Autodesk Fusion 360 part; units mm, degrees
(part 2 of 2)
sketch "草图1 (19)" plane through (0, 50, 0) normal (0, 1, 0) x (1, 0, 0) in component "REF_CASE_FAN_CPU_140x140x25"
  line L0 (156.4, -210, -100) -> (296.4, -210, -100)
  line L1 (296.4, -210, -100) -> (296.4, -350, -100)
  line L2 (296.4, -350, -100) -> (156.4, -350, -100)
  line L3 (156.4, -350, -100) -> (156.4, -210, -100)
extrude "140x140x25 fan envelope'" add sketch "草图1 (19)" along normal blind 25 separate body contours L0 L1 L2 L3 in plane through (0, -50, 0) normal (0, 1, 0) makes body 19 in component "REF_CASE_FAN_CPU_140x140x25"
ref_plane "工作平面2" through (0, 50, 0) normal (0, 1, 0) x (0, 0, 1) in component "REF_CASE_FAN_CPU_140x140x25"
sketch "草图2 (18)" plane through (0, 50, 0) normal (0, 1, 0) x (1, 0, 0) in component "REF_CASE_FAN_CPU_140x140x25"
  circle A0 through (291.4, -280, -100) (193.9, -223.7083, -100) (193.9, -336.2917, -100)
extrude "Rotor opening reference'" cut sketch "草图2 (18)" along normal blind 25 contours A0 in plane through (0, -50, 0) normal (0, 1, 0) bodies 19 in component "REF_CASE_FAN_CPU_140x140x25"
ref_plane "工作平面3" through (0, 0, 278) normal (0, 0, 1) x (1, 0, 0) in component "REF_CASE_FAN_CPU_140x140x25"
sketch "草图3 (14)" plane through (0, 0, 278) normal (0, 0, 1) x (1, 0, 0) in component "REF_CASE_FAN_CPU_140x140x25"
  line L0 (159.4, -38) -> (293.4, -38)
  line L1 (293.4, -38) -> (293.4, -36)
  line L2 (293.4, -36) -> (159.4, -36)
  line L3 (159.4, -36) -> (159.4, -38)
extrude "Rotor reference spoke horizontal'" add sketch "草图3 (14)" along normal blind 4 bodies 19 in component "REF_CASE_FAN_CPU_140x140x25"
ref_plane "工作平面4" through (0, 0, 213) normal (0, 0, 1) x (1, 0, 0) in component "REF_CASE_FAN_CPU_140x140x25"
sketch "草图4 (14)" plane through (0, 0, 213) normal (0, 0, 1) x (1, 0, 0) in component "REF_CASE_FAN_CPU_140x140x25"
  line L0 (224.4, -38) -> (228.4, -38)
  line L1 (228.4, -38) -> (228.4, -36)
  line L2 (228.4, -36) -> (224.4, -36)
  line L3 (224.4, -36) -> (224.4, -38)
extrude "Rotor reference spoke vertical'" add sketch "草图4 (14)" along normal blind 134 bodies 19 in component "REF_CASE_FAN_CPU_140x140x25"
ref_plane "工作平面5" through (0, 38, 0) normal (0, 1, 0) x (0, 0, 1) in component "REF_CASE_FAN_CPU_140x140x25"
sketch "草图5 (14)" plane through (0, 38, 0) normal (0, 1, 0) x (1, 0, 0) in component "REF_CASE_FAN_CPU_140x140x25"
  circle A0 through (242.4, -280, -76) (218.4, -266.1436, -76) (218.4, -293.8564, -76)
extrude "Fan hub reference'" add sketch "草图5 (14)" along normal blind 2 contours A0 in plane through (0, -38, 0) normal (0, 1, 0) bodies 19 in component "REF_CASE_FAN_CPU_140x140x25"
ref_plane "工作平面6" through (0, 50, 0) normal (0, 1, 0) x (0, 0, 1) in component "REF_CASE_FAN_CPU_140x140x25"
sketch "草图6 (10)" plane through (0, 50, 0) normal (0, 1, 0) x (1, 0, 0) in component "REF_CASE_FAN_CPU_140x140x25"
  circle A0 through (166.4, -217.75, -100) (163.025, -215.8014, -100) (163.025, -219.6986, -100)
extrude "Reference fan mounting bore'" cut sketch "草图6 (10)" along normal blind 25 contours A0 in plane through (0, -50, 0) normal (0, 1, 0) bodies 19 in component "REF_CASE_FAN_CPU_140x140x25"
ref_plane "工作平面7" through (0, 50, 0) normal (0, 1, 0) x (0, 0, 1) in component "REF_CASE_FAN_CPU_140x140x25"
sketch "草图7 (7)" plane through (0, 50, 0) normal (0, 1, 0) x (1, 0, 0) in component "REF_CASE_FAN_CPU_140x140x25"
  circle A0 through (166.4, -342.25, -100) (163.025, -340.3014, -100) (163.025, -344.1986, -100)
extrude "Reference fan mounting bore (1)'" cut sketch "草图7 (7)" along normal blind 25 contours A0 in plane through (0, -50, 0) normal (0, 1, 0) bodies 19 in component "REF_CASE_FAN_CPU_140x140x25"
ref_plane "工作平面8" through (0, 50, 0) normal (0, 1, 0) x (0, 0, 1) in component "REF_CASE_FAN_CPU_140x140x25"
sketch "草图8 (6)" plane through (0, 50, 0) normal (0, 1, 0) x (1, 0, 0) in component "REF_CASE_FAN_CPU_140x140x25"
  circle A0 through (290.9, -217.75, -100) (287.525, -215.8014, -100) (287.525, -219.6986, -100)
extrude "Reference fan mounting bore (2)'" cut sketch "草图8 (6)" along normal blind 25 contours A0 in plane through (0, -50, 0) normal (0, 1, 0) bodies 19 in component "REF_CASE_FAN_CPU_140x140x25"
ref_plane "工作平面9" through (0, 50, 0) normal (0, 1, 0) x (0, 0, 1) in component "REF_CASE_FAN_CPU_140x140x25"
sketch "草图9 (6)" plane through (0, 50, 0) normal (0, 1, 0) x (1, 0, 0) in component "REF_CASE_FAN_CPU_140x140x25"
  circle A0 through (290.9, -342.25, -100) (287.525, -340.3014, -100) (287.525, -344.1986, -100)
extrude "Reference fan mounting bore (3)'" cut sketch "草图9 (6)" along normal blind 25 contours A0 in plane through (0, -50, 0) normal (0, 1, 0) bodies 19 in component "REF_CASE_FAN_CPU_140x140x25"
ref_plane "工作平面1" through (0, 0, 279) normal (0, 0, 1) x (1, 0, 0) in component "REF_AIRFLOW_CPU_FRONT_TO_REAR"
sketch "草图1 (20)" plane through (0, 0, 279) normal (0, 0, 1) x (1, 0, 0) in component "REF_AIRFLOW_CPU_FRONT_TO_REAR"
  line L0 (221.4, -75) -> (231.4, -75)
  line L1 (231.4, -75) -> (231.4, -64)
  line L2 (231.4, -64) -> (238.4, -64)
  line L3 (238.4, -64) -> (226.4, -53)
  line L4 (226.4, -53) -> (214.4, -64)
  line L5 (214.4, -64) -> (221.4, -64)
  line L6 (221.4, -64) -> (221.4, -75)
extrude "Front intake direction +Y'" add sketch "草图1 (20)" along normal blind 2 separate body makes body 20 in component "REF_AIRFLOW_CPU_FRONT_TO_REAR"
ref_plane "工作平面1" through (0, 0, 208) normal (0, 0, 1) x (1, 0, 0) in component "REF_BOARD_304.8x243.84_NUMBERED_HOLES"
sketch "草图1 (21)" plane through (0, 0, 208) normal (0, 0, 1) x (1, 0, 0) in component "REF_BOARD_304.8x243.84_NUMBERED_HOLES"
  line L0 (0, 0) -> (304.8, 0)
  line L1 (304.8, 0) -> (304.8, 243.84)
  line L2 (304.8, 243.84) -> (0, 243.84)
  line L3 (0, 243.84) -> (0, 0)
extrude "Motherboard component-side reference" add sketch "草图1 (21)" along normal blind 1.6 separate body makes body 21 in component "REF_BOARD_304.8x243.84_NUMBERED_HOLES"
ref_plane "工作平面2" through (0, 0, 208) normal (0, 0, 1) x (1, 0, 0) in component "REF_BOARD_304.8x243.84_NUMBERED_HOLES"
sketch "草图2 (19)" plane through (0, 0, 208) normal (0, 0, 1) x (1, 0, 0) in component "REF_BOARD_304.8x243.84_NUMBERED_HOLES"
  circle A0 centre (16.51, 233.68) radius 1.98
extrude "Board hole 1" cut sketch "草图2 (19)" along normal blind 1.6 bodies 21 in component "REF_BOARD_304.8x243.84_NUMBERED_HOLES"
ref_plane "工作平面3" through (0, 0, 208) normal (0, 0, 1) x (1, 0, 0) in component "REF_BOARD_304.8x243.84_NUMBERED_HOLES"
sketch "草图3 (15)" plane through (0, 0, 208) normal (0, 0, 1) x (1, 0, 0) in component "REF_BOARD_304.8x243.84_NUMBERED_HOLES"
  circle A0 centre (140.97, 233.68) radius 1.98
extrude "Board hole 2" cut sketch "草图3 (15)" along normal blind 1.6 bodies 21 in component "REF_BOARD_304.8x243.84_NUMBERED_HOLES"
ref_plane "工作平面4" through (0, 0, 208) normal (0, 0, 1) x (1, 0, 0) in component "REF_BOARD_304.8x243.84_NUMBERED_HOLES"
sketch "草图4 (15)" plane through (0, 0, 208) normal (0, 0, 1) x (1, 0, 0) in component "REF_BOARD_304.8x243.84_NUMBERED_HOLES"
  circle A0 centre (298.45, 210.82) radius 1.98
extrude "Board hole 3" cut sketch "草图4 (15)" along normal blind 1.6 bodies 21 in component "REF_BOARD_304.8x243.84_NUMBERED_HOLES"
ref_plane "工作平面5" through (0, 0, 208) normal (0, 0, 1) x (1, 0, 0) in component "REF_BOARD_304.8x243.84_NUMBERED_HOLES"
sketch "草图5 (15)" plane through (0, 0, 208) normal (0, 0, 1) x (1, 0, 0) in component "REF_BOARD_304.8x243.84_NUMBERED_HOLES"
  circle A0 centre (16.51, 78.74) radius 1.98
extrude "Board hole 4" cut sketch "草图5 (15)" along normal blind 1.6 bodies 21 in component "REF_BOARD_304.8x243.84_NUMBERED_HOLES"
ref_plane "工作平面6" through (0, 0, 208) normal (0, 0, 1) x (1, 0, 0) in component "REF_BOARD_304.8x243.84_NUMBERED_HOLES"
sketch "草图6 (11)" plane through (0, 0, 208) normal (0, 0, 1) x (1, 0, 0) in component "REF_BOARD_304.8x243.84_NUMBERED_HOLES"
  circle A0 centre (140.97, 78.74) radius 1.98
extrude "Board hole 5" cut sketch "草图6 (11)" along normal blind 1.6 bodies 21 in component "REF_BOARD_304.8x243.84_NUMBERED_HOLES"
ref_plane "工作平面7" through (0, 0, 208) normal (0, 0, 1) x (1, 0, 0) in component "REF_BOARD_304.8x243.84_NUMBERED_HOLES"
sketch "草图7 (8)" plane through (0, 0, 208) normal (0, 0, 1) x (1, 0, 0) in component "REF_BOARD_304.8x243.84_NUMBERED_HOLES"
  circle A0 centre (298.45, 78.74) radius 1.98
extrude "Board hole 6" cut sketch "草图7 (8)" along normal blind 1.6 bodies 21 in component "REF_BOARD_304.8x243.84_NUMBERED_HOLES"
ref_plane "工作平面8" through (0, 0, 208) normal (0, 0, 1) x (1, 0, 0) in component "REF_BOARD_304.8x243.84_NUMBERED_HOLES"
sketch "草图8 (7)" plane through (0, 0, 208) normal (0, 0, 1) x (1, 0, 0) in component "REF_BOARD_304.8x243.84_NUMBERED_HOLES"
  circle A0 centre (16.51, 6.35) radius 1.98
extrude "Board hole 7" cut sketch "草图8 (7)" along normal blind 1.6 bodies 21 in component "REF_BOARD_304.8x243.84_NUMBERED_HOLES"
ref_plane "工作平面9" through (0, 0, 208) normal (0, 0, 1) x (1, 0, 0) in component "REF_BOARD_304.8x243.84_NUMBERED_HOLES"
sketch "草图9 (7)" plane through (0, 0, 208) normal (0, 0, 1) x (1, 0, 0) in component "REF_BOARD_304.8x243.84_NUMBERED_HOLES"
  circle A0 centre (140.97, 6.35) radius 1.98
extrude "Board hole 8" cut sketch "草图9 (7)" along normal blind 1.6 bodies 21 in component "REF_BOARD_304.8x243.84_NUMBERED_HOLES"
ref_plane "工作平面10" through (0, 0, 208) normal (0, 0, 1) x (1, 0, 0) in component "REF_BOARD_304.8x243.84_NUMBERED_HOLES"
sketch "草图10 (3)" plane through (0, 0, 208) normal (0, 0, 1) x (1, 0, 0) in component "REF_BOARD_304.8x243.84_NUMBERED_HOLES"
  circle A0 centre (298.45, 6.35) radius 1.98
extrude "Board hole 9" cut sketch "草图10 (3)" along normal blind 1.6 bodies 21 in component "REF_BOARD_304.8x243.84_NUMBERED_HOLES"
ref_plane "工作平面1" through (0, 0, 209.6) normal (0, 0, 1) x (1, 0, 0) in component "REF_CPU_RIGHT"
sketch "草图1 (22)" plane through (0, 0, 209.6) normal (0, 0, 1) x (1, 0, 0) in component "REF_CPU_RIGHT"
  line L0 (185, 108.84) -> (260, 108.84)
  line L1 (260, 108.84) -> (260, 178.84)
  line L2 (260, 178.84) -> (185, 178.84)
  line L3 (185, 178.84) -> (185, 108.84)
extrude "CPU position reference only" add sketch "草图1 (22)" along normal blind 5 separate body makes body 22 in component "REF_CPU_RIGHT"
ref_plane "工作平面1" through (0, 0, 209.6) normal (0, 0, 1) x (1, 0, 0) in component "REF_MEMORY_RIGHT_FRONT"
sketch "草图1 (23)" plane through (0, 0, 209.6) normal (0, 0, 1) x (1, 0, 0) in component "REF_MEMORY_RIGHT_FRONT"
  line L0 (150, 57.24) -> (285, 57.24)
  line L1 (285, 57.24) -> (285, 62.44)
  line L2 (285, 62.44) -> (150, 62.44)
  line L3 (150, 62.44) -> (150, 57.24)
extrude "DIMM position reference" add sketch "草图1 (23)" along normal blind 12.4 separate body makes body 23 in component "REF_MEMORY_RIGHT_FRONT"
ref_plane "工作平面2" through (0, 0, 209.6) normal (0, 0, 1) x (1, 0, 0) in component "REF_MEMORY_RIGHT_FRONT"
sketch "草图2 (20)" plane through (0, 0, 209.6) normal (0, 0, 1) x (1, 0, 0) in component "REF_MEMORY_RIGHT_FRONT"
  line L0 (150, 47.24) -> (285, 47.24)
  line L1 (285, 47.24) -> (285, 52.44)
  line L2 (285, 52.44) -> (150, 52.44)
  line L3 (150, 52.44) -> (150, 47.24)
extrude "DIMM position reference (1)" add sketch "草图2 (20)" along normal blind 12.4 separate body makes body 24 in component "REF_MEMORY_RIGHT_FRONT"
ref_plane "工作平面3" through (0, 0, 209.6) normal (0, 0, 1) x (1, 0, 0) in component "REF_MEMORY_RIGHT_FRONT"
sketch "草图3 (16)" plane through (0, 0, 209.6) normal (0, 0, 1) x (1, 0, 0) in component "REF_MEMORY_RIGHT_FRONT"
  line L0 (150, 37.24) -> (285, 37.24)
  line L1 (285, 37.24) -> (285, 42.44)
  line L2 (285, 42.44) -> (150, 42.44)
  line L3 (150, 42.44) -> (150, 37.24)
extrude "DIMM position reference (2)" add sketch "草图3 (16)" along normal blind 12.4 separate body makes body 25 in component "REF_MEMORY_RIGHT_FRONT"
ref_plane "工作平面4" through (0, 0, 209.6) normal (0, 0, 1) x (1, 0, 0) in component "REF_MEMORY_RIGHT_FRONT"
sketch "草图4 (16)" plane through (0, 0, 209.6) normal (0, 0, 1) x (1, 0, 0) in component "REF_MEMORY_RIGHT_FRONT"
  line L0 (150, 27.24) -> (285, 27.24)
  line L1 (285, 27.24) -> (285, 32.44)
  line L2 (285, 32.44) -> (150, 32.44)
  line L3 (150, 32.44) -> (150, 27.24)
extrude "DIMM position reference (3)" add sketch "草图4 (16)" along normal blind 12.4 separate body makes body 26 in component "REF_MEMORY_RIGHT_FRONT"
ref_plane "工作平面1" through (0, 0, 209.6) normal (0, 0, 1) x (1, 0, 0) in component "REF_PRIMARY_PCIE_X126.4_APPROX"
sketch "草图1 (24)" plane through (0, 0, 209.6) normal (0, 0, 1) x (1, 0, 0) in component "REF_PRIMARY_PCIE_X126.4_APPROX"
  line L0 (122.4, 96.84) -> (130.4, 96.84)
  line L1 (130.4, 96.84) -> (130.4, 201.84)
  line L2 (130.4, 201.84) -> (122.4, 201.84)
  line L3 (122.4, 201.84) -> (122.4, 96.84)
extrude "Primary GPU slot approximate" add sketch "草图1 (24)" along normal blind 10 separate body makes body 27 in component "REF_PRIMARY_PCIE_X126.4_APPROX"
ref_plane "工作平面1" through (0, 0, 209.6) normal (0, 0, 1) x (1, 0, 0) in component "REF_SECOND_LONG_PCIE_X60_APPROX"
sketch "草图1 (25)" plane through (0, 0, 209.6) normal (0, 0, 1) x (1, 0, 0) in component "REF_SECOND_LONG_PCIE_X60_APPROX"
  line L0 (56, 96.84) -> (64, 96.84)
  line L1 (64, 96.84) -> (64, 201.84)
  line L2 (64, 201.84) -> (56, 201.84)
  line L3 (56, 201.84) -> (56, 96.84)
extrude "Second long PCIe approximate" add sketch "草图1 (25)" along normal blind 10 separate body makes body 28 in component "REF_SECOND_LONG_PCIE_X60_APPROX"
ref_plane "工作平面1" through (0, 0, 221) normal (0, 0, 1) x (1, 0, 0) in component "REF_GPU_FANS_TO_MINUS_X"
sketch "草图1 (26)" plane through (0, 0, 221) normal (0, 0, 1) x (1, 0, 0) in component "REF_GPU_FANS_TO_MINUS_X"
  line L0 (88.4, 20.84) -> (128.4, 20.84)
  line L1 (128.4, 20.84) -> (128.4, 243.84)
  line L2 (128.4, 243.84) -> (88.4, 243.84)
  line L3 (88.4, 243.84) -> (88.4, 20.84)
extrude "GPU body 40 x 223 x 114" add sketch "草图1 (26)" along normal blind 114 separate body makes body 29 in component "REF_GPU_FANS_TO_MINUS_X"
ref_plane "工作平面1" through (88.1, 0, 0) normal (1, 0, 0) x (0, 1, 0) in component "REF_GPU_FAN_MARKERS_MINUS_X"
sketch "草图1 (27)" plane through (88.1, 0, 0) normal (1, 0, 0) x (0, 0, -1) in component "REF_GPU_FAN_MARKERS_MINUS_X"
  circle A0 centre (-278, 75) radius 46
extrude "GPU fan faces away from PSU fan" add sketch "草图1 (27)" along normal blind 0.3 separate body makes body 30 in component "REF_GPU_FAN_MARKERS_MINUS_X"
ref_plane "工作平面2" through (88.1, 0, 0) normal (1, 0, 0) x (0, 1, 0) in component "REF_GPU_FAN_MARKERS_MINUS_X"
sketch "草图2 (21)" plane through (88.1, 0, 0) normal (1, 0, 0) x (0, 0, -1) in component "REF_GPU_FAN_MARKERS_MINUS_X"
  circle A0 centre (-278, 180) radius 46
extrude "GPU fan faces away from PSU fan (1)" add sketch "草图2 (21)" along normal blind 0.3 separate body makes body 31 in component "REF_GPU_FAN_MARKERS_MINUS_X"
ref_plane "工作平面1" through (0, 14.4, 0) normal (0, 1, 0) x (0, 0, 1) in component "11_LOWER_FRONT_COVER_PCI_HALF"
sketch "草图1 (28)" plane through (0, 14.4, 0) normal (0, 1, 0) x (1, 0, 0) in component "11_LOWER_FRONT_COVER_PCI_HALF"
  line L0 (7.9258, -8, -28.8) -> (152.1, -8, -28.8)
  line L1 (152.1, -8, -28.8) -> (152.1, -182, -28.8)
  line L2 (152.1, -182, -28.8) -> (-3.4758, -182, -28.8)
  line L3 (-3.4758, -182, -28.8) -> (7.9258, -8, -28.8)
extrude "3 mm PETG lower front cover - follows PCI side taper" add sketch "草图1 (28)" along normal blind 3 separate body contours L0 L1 L2 L3 in plane through (0, -14.4, 0) normal (0, 1, 0) makes body 32 in component "11_LOWER_FRONT_COVER_PCI_HALF"
ref_plane "工作平面1" through (0, 14.4, 0) normal (0, 1, 0) x (0, 0, 1) in component "11_LOWER_FRONT_COVER_CPU_HALF"
sketch "草图1 (29)" plane through (0, 14.4, 0) normal (0, 1, 0) x (1, 0, 0) in component "11_LOWER_FRONT_COVER_CPU_HALF"
  line L0 (152.7, -8, -28.8) -> (298.45, -8, -28.8)
  line L1 (298.45, -8, -28.8) -> (298.45, -182, -28.8)
  line L2 (298.45, -182, -28.8) -> (152.7, -182, -28.8)
  line L3 (152.7, -182, -28.8) -> (152.7, -8, -28.8)
extrude "3 mm PETG lower front cover - straight CPU edge" add sketch "草图1 (29)" along normal blind 3 separate body contours L0 L1 L2 L3 in plane through (0, -14.4, 0) normal (0, 1, 0) makes body 33 in component "11_LOWER_FRONT_COVER_CPU_HALF"
ref_plane "工作平面2" through (0, 14.4, 0) normal (0, 1, 0) x (0, 0, 1) in component "11_LOWER_FRONT_COVER_PCI_HALF"
sketch "草图2 (22)" plane through (0, 14.4, 0) normal (0, 1, 0) x (1, 0, 0) in component "11_LOWER_FRONT_COVER_PCI_HALF"
  line L0 (18, -180, -28.8) -> (32, -180, -28.8)
  line L1 (32, -180, -28.8) -> (32, -196, -28.8)
  line L2 (32, -196, -28.8) -> (18, -196, -28.8)
  line L3 (18, -196, -28.8) -> (18, -180, -28.8)
extrude "Upper removable mounting tab" add sketch "草图2 (22)" along normal blind 3 contours L0 L1 L2 L3 in plane through (0, -14.4, 0) normal (0, 1, 0) bodies 32 in component "11_LOWER_FRONT_COVER_PCI_HALF"
ref_plane "工作平面3" through (0, 11.4, 0) normal (0, 1, 0) x (0, 0, 1) in component "11_LOWER_FRONT_COVER_PCI_HALF"
sketch "草图3 (17)" plane through (0, 11.4, 0) normal (0, 1, 0) x (1, 0, 0) in component "11_LOWER_FRONT_COVER_PCI_HALF"
  circle A0 through (29, -192.5, -22.8) (23, -189.0359, -22.8) (23, -195.9641, -22.8)
extrude "Upper mounting stand-off" add sketch "草图3 (17)" along normal blind 8.75 contours A0 in plane through (0, -11.4, 0) normal (0, 1, 0) bodies 32 in component "11_LOWER_FRONT_COVER_PCI_HALF"
ref_plane "工作平面4" through (0, 14.4, 0) normal (0, 1, 0) x (0, 0, 1) in component "11_LOWER_FRONT_COVER_PCI_HALF"
sketch "草图4 (17)" plane through (0, 14.4, 0) normal (0, 1, 0) x (1, 0, 0) in component "11_LOWER_FRONT_COVER_PCI_HALF"
  circle A0 through (26.7, -192.5, -28.8) (24.15, -191.0278, -28.8) (24.15, -193.9722, -28.8)
extrude "Upper M3x16 screw clearance" cut sketch "草图4 (17)" along normal blind 11.75 contours A0 in plane through (0, -14.4, 0) normal (0, 1, 0) bodies 32 in component "11_LOWER_FRONT_COVER_PCI_HALF"
ref_plane "工作平面10" through (0, 2.65, 0) normal (0, 1, 0) x (0, 0, 1) in component "03_FRONT_MOTHERBOARD_BEAM"
sketch "草图10 (4)" plane through (0, 2.65, 0) normal (0, 1, 0) x (1, 0, 0) in component "03_FRONT_MOTHERBOARD_BEAM"
  circle A0 through (27.35, -192.5, -5.3) (23.825, -190.4648, -5.3) (23.825, -194.5352, -5.3)
extrude "M3 short heat insert for removable front cover" cut sketch "草图10 (4)" along normal blind 4.7 contours A0 in plane through (0, -2.65, 0) normal (0, 1, 0) bodies 9 in component "03_FRONT_MOTHERBOARD_BEAM"
ref_plane "工作平面2" through (0, 14.4, 0) normal (0, 1, 0) x (0, 0, 1) in component "11_LOWER_FRONT_COVER_CPU_HALF"
sketch "草图2 (23)" plane through (0, 14.4, 0) normal (0, 1, 0) x (1, 0, 0) in component "11_LOWER_FRONT_COVER_CPU_HALF"
  line L0 (279, -180, -28.8) -> (293, -180, -28.8)
  line L1 (293, -180, -28.8) -> (293, -196, -28.8)
  line L2 (293, -196, -28.8) -> (279, -196, -28.8)
  line L3 (279, -196, -28.8) -> (279, -180, -28.8)
extrude "Upper removable mounting tab'" add sketch "草图2 (23)" along normal blind 3 contours L0 L1 L2 L3 in plane through (0, -14.4, 0) normal (0, 1, 0) bodies 33 in component "11_LOWER_FRONT_COVER_CPU_HALF"
ref_plane "工作平面3" through (0, 11.4, 0) normal (0, 1, 0) x (0, 0, 1) in component "11_LOWER_FRONT_COVER_CPU_HALF"
sketch "草图3 (18)" plane through (0, 11.4, 0) normal (0, 1, 0) x (1, 0, 0) in component "11_LOWER_FRONT_COVER_CPU_HALF"
  circle A0 through (290, -192.5, -22.8) (284, -189.0359, -22.8) (284, -195.9641, -22.8)
extrude "Upper mounting stand-off'" add sketch "草图3 (18)" along normal blind 8.75 contours A0 in plane through (0, -11.4, 0) normal (0, 1, 0) bodies 33 in component "11_LOWER_FRONT_COVER_CPU_HALF"
ref_plane "工作平面4" through (0, 14.4, 0) normal (0, 1, 0) x (0, 0, 1) in component "11_LOWER_FRONT_COVER_CPU_HALF"
sketch "草图4 (18)" plane through (0, 14.4, 0) normal (0, 1, 0) x (1, 0, 0) in component "11_LOWER_FRONT_COVER_CPU_HALF"
  circle A0 through (287.7, -192.5, -28.8) (285.15, -191.0278, -28.8) (285.15, -193.9722, -28.8)
extrude "Upper M3x16 screw clearance'" cut sketch "草图4 (18)" along normal blind 11.75 contours A0 in plane through (0, -14.4, 0) normal (0, 1, 0) bodies 33 in component "11_LOWER_FRONT_COVER_CPU_HALF"
ref_plane "工作平面11" through (0, 2.65, 0) normal (0, 1, 0) x (0, 0, 1) in component "03_FRONT_MOTHERBOARD_BEAM"
sketch "草图11" plane through (0, 2.65, 0) normal (0, 1, 0) x (1, 0, 0) in component "03_FRONT_MOTHERBOARD_BEAM"
  circle A0 through (288.35, -192.5, -5.3) (284.825, -190.4648, -5.3) (284.825, -194.5352, -5.3)
extrude "M3 short heat insert for removable front cover (1)" cut sketch "草图11" along normal blind 4.7 contours A0 in plane through (0, -2.65, 0) normal (0, 1, 0) bodies 9 in component "03_FRONT_MOTHERBOARD_BEAM"
ref_plane "工作平面5" through (0, 11.4, 0) normal (0, 1, 0) x (0, 0, 1) in component "11_LOWER_FRONT_COVER_PCI_HALF"
sketch "草图5 (16)" plane through (0, 11.4, 0) normal (0, 1, 0) x (1, 0, 0) in component "11_LOWER_FRONT_COVER_PCI_HALF"
  circle A0 through (21.5, -20, -22.8) (15.5, -16.5359, -22.8) (15.5, -23.4641, -22.8)
extrude "Lower mounting spacer" add sketch "草图5 (16)" along normal blind 1.4 contours A0 in plane through (0, -11.4, 0) normal (0, 1, 0) bodies 32 in component "11_LOWER_FRONT_COVER_PCI_HALF"
ref_plane "工作平面6" through (0, 14.4, 0) normal (0, 1, 0) x (0, 0, 1) in component "11_LOWER_FRONT_COVER_PCI_HALF"
sketch "草图6 (12)" plane through (0, 14.4, 0) normal (0, 1, 0) x (1, 0, 0) in component "11_LOWER_FRONT_COVER_PCI_HALF"
  circle A0 through (19.2, -20, -28.8) (16.65, -18.5278, -28.8) (16.65, -21.4722, -28.8)
extrude "Lower M3x8 screw clearance" cut sketch "草图6 (12)" along normal blind 4.4 contours A0 in plane through (0, -14.4, 0) normal (0, 1, 0) bodies 32 in component "11_LOWER_FRONT_COVER_PCI_HALF"
ref_plane "工作平面6" through (0, 10, 0) normal (0, 1, 0) x (0, 0, 1) in component "01_PCI_front_INSET_SIDE"
sketch "草图6 (13)" plane through (0, 10, 0) normal (0, 1, 0) x (1, 0, 0) in component "01_PCI_front_INSET_SIDE"
  circle A0 through (19.85, -20, -20) (16.325, -17.9648, -20) (16.325, -22.0352, -20)
extrude "M3 short heat insert for removable front cover'" cut sketch "草图6 (13)" along normal blind 4.7 contours A0 in plane through (0, -10, 0) normal (0, 1, 0) bodies 1 in component "01_PCI_front_INSET_SIDE"
ref_plane "工作平面5" through (0, 11.4, 0) normal (0, 1, 0) x (0, 0, 1) in component "11_LOWER_FRONT_COVER_CPU_HALF"
sketch "草图5 (17)" plane through (0, 11.4, 0) normal (0, 1, 0) x (1, 0, 0) in component "11_LOWER_FRONT_COVER_CPU_HALF"
  circle A0 through (294.45, -20, -22.8) (288.45, -16.5359, -22.8) (288.45, -23.4641, -22.8)
extrude "Lower mounting spacer'" add sketch "草图5 (17)" along normal blind 1.4 contours A0 in plane through (0, -11.4, 0) normal (0, 1, 0) bodies 33 in component "11_LOWER_FRONT_COVER_CPU_HALF"
ref_plane "工作平面6" through (0, 14.4, 0) normal (0, 1, 0) x (0, 0, 1) in component "11_LOWER_FRONT_COVER_CPU_HALF"
sketch "草图6 (14)" plane through (0, 14.4, 0) normal (0, 1, 0) x (1, 0, 0) in component "11_LOWER_FRONT_COVER_CPU_HALF"
  circle A0 through (292.15, -20, -28.8) (289.6, -18.5278, -28.8) (289.6, -21.4722, -28.8)
extrude "Lower M3x8 screw clearance'" cut sketch "草图6 (14)" along normal blind 4.4 contours A0 in plane through (0, -14.4, 0) normal (0, 1, 0) bodies 33 in component "11_LOWER_FRONT_COVER_CPU_HALF"
ref_plane "工作平面6" through (0, 10, 0) normal (0, 1, 0) x (0, 0, 1) in component "01_CPU_front_VERTICAL_SIDE"
sketch "草图6 (15)" plane through (0, 10, 0) normal (0, 1, 0) x (1, 0, 0) in component "01_CPU_front_VERTICAL_SIDE"
  circle A0 through (292.8, -20, -20) (289.275, -17.9648, -20) (289.275, -22.0352, -20)
extrude "M3 short heat insert for removable front cover''" cut sketch "草图6 (15)" along normal blind 4.7 contours A0 in plane through (0, -10, 0) normal (0, 1, 0) bodies 3 in component "01_CPU_front_VERTICAL_SIDE"
ref_plane "工作平面7" through (0, 11.4, 0) normal (0, 1, 0) x (0, 0, 1) in component "11_LOWER_FRONT_COVER_PCI_HALF"
sketch "草图7 (9)" plane through (0, 11.4, 0) normal (0, 1, 0) x (1, 0, 0) in component "11_LOWER_FRONT_COVER_PCI_HALF"
  line L0 (148, -37, -22.8) -> (162, -37, -22.8)
  line L1 (162, -37, -22.8) -> (162, -53, -22.8)
  line L2 (162, -53, -22.8) -> (148, -53, -22.8)
  line L3 (148, -53, -22.8) -> (148, -37, -22.8)
extrude "Hidden center seam joining lug" add sketch "草图7 (9)" along normal blind 6 contours L0 L1 L2 L3 in plane through (0, -11.4, 0) normal (0, 1, 0) bodies 32 in component "11_LOWER_FRONT_COVER_PCI_HALF"
ref_plane "工作平面8" through (0, 11.4, 0) normal (0, 1, 0) x (0, 0, 1) in component "11_LOWER_FRONT_COVER_PCI_HALF"
sketch "草图8 (8)" plane through (0, 11.4, 0) normal (0, 1, 0) x (1, 0, 0) in component "11_LOWER_FRONT_COVER_PCI_HALF"
  circle A0 through (159.85, -45, -22.8) (156.325, -42.9648, -22.8) (156.325, -47.0352, -22.8)
extrude "M3 short heat insert in seam lug" cut sketch "草图8 (8)" along normal blind 4.7 contours A0 in plane through (0, -11.4, 0) normal (0, 1, 0) bodies 32 in component "11_LOWER_FRONT_COVER_PCI_HALF"
ref_plane "工作平面7" through (0, 14.4, 0) normal (0, 1, 0) x (0, 0, 1) in component "11_LOWER_FRONT_COVER_CPU_HALF"
sketch "草图7 (10)" plane through (0, 14.4, 0) normal (0, 1, 0) x (1, 0, 0) in component "11_LOWER_FRONT_COVER_CPU_HALF"
  circle A0 through (159.2, -45, -28.8) (156.65, -43.5278, -28.8) (156.65, -46.4722, -28.8)
extrude "M3x6 center seam screw clearance" cut sketch "草图7 (10)" along normal blind 3 contours A0 in plane through (0, -14.4, 0) normal (0, 1, 0) bodies 33 in component "11_LOWER_FRONT_COVER_CPU_HALF"
ref_plane "工作平面9" through (0, 11.4, 0) normal (0, 1, 0) x (0, 0, 1) in component "11_LOWER_FRONT_COVER_PCI_HALF"
sketch "草图9 (8)" plane through (0, 11.4, 0) normal (0, 1, 0) x (1, 0, 0) in component "11_LOWER_FRONT_COVER_PCI_HALF"
  line L0 (148, -142, -22.8) -> (162, -142, -22.8)
  line L1 (162, -142, -22.8) -> (162, -158, -22.8)
  line L2 (162, -158, -22.8) -> (148, -158, -22.8)
  line L3 (148, -158, -22.8) -> (148, -142, -22.8)
extrude "Hidden center seam joining lug (1)" add sketch "草图9 (8)" along normal blind 6 contours L0 L1 L2 L3 in plane through (0, -11.4, 0) normal (0, 1, 0) bodies 32 in component "11_LOWER_FRONT_COVER_PCI_HALF"
ref_plane "工作平面10" through (0, 11.4, 0) normal (0, 1, 0) x (0, 0, 1) in component "11_LOWER_FRONT_COVER_PCI_HALF"
sketch "草图10 (5)" plane through (0, 11.4, 0) normal (0, 1, 0) x (1, 0, 0) in component "11_LOWER_FRONT_COVER_PCI_HALF"
  circle A0 through (159.85, -150, -22.8) (156.325, -147.9648, -22.8) (156.325, -152.0352, -22.8)
extrude "M3 short heat insert in seam lug (1)" cut sketch "草图10 (5)" along normal blind 4.7 contours A0 in plane through (0, -11.4, 0) normal (0, 1, 0) bodies 32 in component "11_LOWER_FRONT_COVER_PCI_HALF"
ref_plane "工作平面8" through (0, 14.4, 0) normal (0, 1, 0) x (0, 0, 1) in component "11_LOWER_FRONT_COVER_CPU_HALF"
sketch "草图8 (9)" plane through (0, 14.4, 0) normal (0, 1, 0) x (1, 0, 0) in component "11_LOWER_FRONT_COVER_CPU_HALF"
  circle A0 through (159.2, -150, -28.8) (156.65, -148.5278, -28.8) (156.65, -151.4722, -28.8)
extrude "M3x6 center seam screw clearance (1)" cut sketch "草图8 (9)" along normal blind 3 contours A0 in plane through (0, -14.4, 0) normal (0, 1, 0) bodies 33 in component "11_LOWER_FRONT_COVER_CPU_HALF"
ref_plane "工作平面7" through (0, 10, 0) normal (0, 1, 0) x (0, 0, 1) in component "01_CPU_front_VERTICAL_SIDE"
sketch "草图7 (11)" plane through (0, 10, 0) normal (0, 1, 0) x (1, 0, 0) in component "01_CPU_front_VERTICAL_SIDE"
  circle A0 through (290.2, -192.5, -20) (283.9, -188.8627, -20) (283.9, -196.1373, -20)
extrude "Upper cover stand-off clearance" cut sketch "草图7 (11)" along normal blind 7.35 contours A0 in plane through (0, -10, 0) normal (0, 1, 0) bodies 3 in component "01_CPU_front_VERTICAL_SIDE"
ref_plane "工作平面7" through (0, 0, 0) normal (0, 0, 1) x (1, 0, 0) in component "01_PCI_front_INSET_SIDE"
sketch "草图7 (12)" plane through (0, 0, 0) normal (0, 0, 1) x (1, 0, 0) in component "01_PCI_front_INSET_SIDE"
  line L0 (-10, 29.92) -> (320, 29.92)
  line L1 (320, 29.92) -> (320, 49.92)
  line L2 (320, 49.92) -> (-10, 49.92)
  line L3 (-10, 49.92) -> (-10, 29.92)
extrude "Recess for relocated crossbar outside PSU intake" cut sketch "草图7 (12)" along normal blind 8 bodies 1 in component "01_PCI_front_INSET_SIDE"
ref_plane "工作平面6" through (0, 0, 0) normal (0, 0, 1) x (1, 0, 0) in component "01_PCI_rear_INSET_SIDE"
sketch "草图6 (16)" plane through (0, 0, 0) normal (0, 0, 1) x (1, 0, 0) in component "01_PCI_rear_INSET_SIDE"
  line L0 (-10, 193.92) -> (320, 193.92)
  line L1 (320, 193.92) -> (320, 213.92)
  line L2 (320, 213.92) -> (-10, 213.92)
  line L3 (-10, 213.92) -> (-10, 193.92)
extrude "Recess for relocated crossbar outside PSU intake'" cut sketch "草图6 (16)" along normal blind 8 bodies 2 in component "01_PCI_rear_INSET_SIDE"
ref_plane "工作平面8" through (0, 0, 0) normal (0, 0, 1) x (1, 0, 0) in component "01_CPU_front_VERTICAL_SIDE"
sketch "草图8 (10)" plane through (0, 0, 0) normal (0, 0, 1) x (1, 0, 0) in component "01_CPU_front_VERTICAL_SIDE"
  line L0 (-10, 29.92) -> (320, 29.92)
  line L1 (320, 29.92) -> (320, 49.92)
  line L2 (320, 49.92) -> (-10, 49.92)
  line L3 (-10, 49.92) -> (-10, 29.92)
extrude "Recess for relocated crossbar outside PSU intake''" cut sketch "草图8 (10)" along normal blind 8 bodies 3 in component "01_CPU_front_VERTICAL_SIDE"
ref_plane "工作平面6" through (0, 0, 0) normal (0, 0, 1) x (1, 0, 0) in component "01_CPU_rear_VERTICAL_SIDE"
sketch "草图6 (17)" plane through (0, 0, 0) normal (0, 0, 1) x (1, 0, 0) in component "01_CPU_rear_VERTICAL_SIDE"
  line L0 (-10, 193.92) -> (320, 193.92)
  line L1 (320, 193.92) -> (320, 213.92)
  line L2 (320, 213.92) -> (-10, 213.92)
  line L3 (-10, 213.92) -> (-10, 193.92)
extrude "Recess for relocated crossbar outside PSU intake'''" cut sketch "草图6 (17)" along normal blind 8 bodies 4 in component "01_CPU_rear_VERTICAL_SIDE"
ref_plane "工作平面1" through (0, 0, 0) normal (0, 0, 1) x (1, 0, 0) in component "04_front_GROUND_BAR_290mm_FLAT_PSU"
sketch "草图1 (30)" plane through (0, 0, 0) normal (0, 0, 1) x (1, 0, 0) in component "04_front_GROUND_BAR_290mm_FLAT_PSU"
  line L0 (8.45, 29.92) -> (298.45, 29.92)
  line L1 (298.45, 29.92) -> (298.45, 49.92)
  line L2 (298.45, 49.92) -> (8.45, 49.92)
  line L3 (8.45, 49.92) -> (8.45, 29.92)
extrude "290 mm ground bar clear of intake circle" add sketch "草图1 (30)" along normal blind 8 separate body makes body 34 in component "04_front_GROUND_BAR_290mm_FLAT_PSU"
ref_plane "工作平面1" through (0, 0, 0) normal (0, 0, 1) x (1, 0, 0) in component "04_rear_GROUND_BAR_290mm_FLAT_PSU"
sketch "草图1 (31)" plane through (0, 0, 0) normal (0, 0, 1) x (1, 0, 0) in component "04_rear_GROUND_BAR_290mm_FLAT_PSU"
  line L0 (8.45, 193.92) -> (298.45, 193.92)
  line L1 (298.45, 193.92) -> (298.45, 213.92)
  line L2 (298.45, 213.92) -> (8.45, 213.92)
  line L3 (8.45, 213.92) -> (8.45, 193.92)
extrude "290 mm ground bar clear of intake circle'" add sketch "草图1 (31)" along normal blind 8 separate body makes body 35 in component "04_rear_GROUND_BAR_290mm_FLAT_PSU"
ref_plane "工作平面1" through (0, 0, 24) normal (0, 0, 1) x (1, 0, 0) in component "05_CENTERED_FLAT_PSU_CRADLE_OPEN_INTAKE"
sketch "草图1 (32)" plane through (0, 0, 24) normal (0, 0, 1) x (1, 0, 0) in component "05_CENTERED_FLAT_PSU_CRADLE_OPEN_INTAKE"
  line L0 (73.4, 29.92) -> (85.4, 29.92)
  line L1 (85.4, 29.92) -> (85.4, 213.92)
  line L2 (85.4, 213.92) -> (73.4, 213.92)
  line L3 (73.4, 213.92) -> (73.4, 29.92)
extrude "PCI side edge-bearing runner" add sketch "草图1 (32)" along normal blind 6 separate body makes body 36 in component "05_CENTERED_FLAT_PSU_CRADLE_OPEN_INTAKE"
ref_plane "工作平面2" through (0, 0, 24) normal (0, 0, 1) x (1, 0, 0) in component "05_CENTERED_FLAT_PSU_CRADLE_OPEN_INTAKE"
sketch "草图2 (24)" plane through (0, 0, 24) normal (0, 0, 1) x (1, 0, 0) in component "05_CENTERED_FLAT_PSU_CRADLE_OPEN_INTAKE"
  line L0 (85.4, 29.92) -> (231.4, 29.92)
  line L1 (231.4, 29.92) -> (231.4, 41.92)
  line L2 (231.4, 41.92) -> (85.4, 41.92)
  line L3 (85.4, 41.92) -> (85.4, 29.92)
extrude "Front tie outside intake projection" add sketch "草图2 (24)" along normal blind 6 bodies 36 in component "05_CENTERED_FLAT_PSU_CRADLE_OPEN_INTAKE"
ref_plane "工作平面3" through (0, 0, 24) normal (0, 0, 1) x (1, 0, 0) in component "05_CENTERED_FLAT_PSU_CRADLE_OPEN_INTAKE"
sketch "草图3 (19)" plane through (0, 0, 24) normal (0, 0, 1) x (1, 0, 0) in component "05_CENTERED_FLAT_PSU_CRADLE_OPEN_INTAKE"
  line L0 (219.4, 41.92) -> (231.4, 41.92)
  line L1 (231.4, 41.92) -> (231.4, 213.92)
  line L2 (231.4, 213.92) -> (219.4, 213.92)
  line L3 (219.4, 213.92) -> (219.4, 41.92)
extrude "CPU side edge-bearing runner" add sketch "草图3 (19)" along normal blind 6 bodies 36 in component "05_CENTERED_FLAT_PSU_CRADLE_OPEN_INTAKE"
ref_plane "工作平面4" through (0, 0, 24) normal (0, 0, 1) x (1, 0, 0) in component "05_CENTERED_FLAT_PSU_CRADLE_OPEN_INTAKE"
sketch "草图4 (19)" plane through (0, 0, 24) normal (0, 0, 1) x (1, 0, 0) in component "05_CENTERED_FLAT_PSU_CRADLE_OPEN_INTAKE"
  line L0 (85.4, 201.92) -> (219.4, 201.92)
  line L1 (219.4, 201.92) -> (219.4, 213.92)
  line L2 (219.4, 213.92) -> (85.4, 213.92)
  line L3 (85.4, 213.92) -> (85.4, 201.92)
extrude "Rear tie outside intake projection" add sketch "草图4 (19)" along normal blind 6 bodies 36 in component "05_CENTERED_FLAT_PSU_CRADLE_OPEN_INTAKE"
ref_plane "工作平面5" through (0, 0, 8) normal (0, 0, 1) x (1, 0, 0) in component "05_CENTERED_FLAT_PSU_CRADLE_OPEN_INTAKE"
sketch "草图5 (18)" plane through (0, 0, 8) normal (0, 0, 1) x (1, 0, 0) in component "05_CENTERED_FLAT_PSU_CRADLE_OPEN_INTAKE"
  line L0 (74.4, 34.92) -> (84.4, 34.92)
  line L1 (84.4, 34.92) -> (84.4, 44.92)
  line L2 (84.4, 44.92) -> (74.4, 44.92)
  line L3 (74.4, 44.92) -> (74.4, 34.92)
extrude "Short load foot to ground crossbar" add sketch "草图5 (18)" along normal blind 16 bodies 36 in component "05_CENTERED_FLAT_PSU_CRADLE_OPEN_INTAKE"
ref_plane "工作平面6" through (0, 0, 8) normal (0, 0, 1) x (1, 0, 0) in component "05_CENTERED_FLAT_PSU_CRADLE_OPEN_INTAKE"
sketch "草图6 (18)" plane through (0, 0, 8) normal (0, 0, 1) x (1, 0, 0) in component "05_CENTERED_FLAT_PSU_CRADLE_OPEN_INTAKE"
  line L0 (74.4, 198.92) -> (84.4, 198.92)
  line L1 (84.4, 198.92) -> (84.4, 208.92)
  line L2 (84.4, 208.92) -> (74.4, 208.92)
  line L3 (74.4, 208.92) -> (74.4, 198.92)
extrude "Short load foot to ground crossbar (1)" add sketch "草图6 (18)" along normal blind 16 bodies 36 in component "05_CENTERED_FLAT_PSU_CRADLE_OPEN_INTAKE"
ref_plane "工作平面7" through (0, 0, 8) normal (0, 0, 1) x (1, 0, 0) in component "05_CENTERED_FLAT_PSU_CRADLE_OPEN_INTAKE"
sketch "草图7 (13)" plane through (0, 0, 8) normal (0, 0, 1) x (1, 0, 0) in component "05_CENTERED_FLAT_PSU_CRADLE_OPEN_INTAKE"
  line L0 (220.4, 34.92) -> (230.4, 34.92)
  line L1 (230.4, 34.92) -> (230.4, 44.92)
  line L2 (230.4, 44.92) -> (220.4, 44.92)
  line L3 (220.4, 44.92) -> (220.4, 34.92)
extrude "Short load foot to ground crossbar (2)" add sketch "草图7 (13)" along normal blind 16 bodies 36 in component "05_CENTERED_FLAT_PSU_CRADLE_OPEN_INTAKE"
ref_plane "工作平面8" through (0, 0, 8) normal (0, 0, 1) x (1, 0, 0) in component "05_CENTERED_FLAT_PSU_CRADLE_OPEN_INTAKE"
sketch "草图8 (11)" plane through (0, 0, 8) normal (0, 0, 1) x (1, 0, 0) in component "05_CENTERED_FLAT_PSU_CRADLE_OPEN_INTAKE"
  line L0 (220.4, 198.92) -> (230.4, 198.92)
  line L1 (230.4, 198.92) -> (230.4, 208.92)
  line L2 (230.4, 208.92) -> (220.4, 208.92)
  line L3 (220.4, 208.92) -> (220.4, 198.92)
extrude "Short load foot to ground crossbar (3)" add sketch "草图8 (11)" along normal blind 16 bodies 36 in component "05_CENTERED_FLAT_PSU_CRADLE_OPEN_INTAKE"
ref_plane "工作平面9" through (0, 0, 30) normal (0, 0, 1) x (1, 0, 0) in component "05_CENTERED_FLAT_PSU_CRADLE_OPEN_INTAKE"
sketch "草图9 (9)" plane through (0, 0, 30) normal (0, 0, 1) x (1, 0, 0) in component "05_CENTERED_FLAT_PSU_CRADLE_OPEN_INTAKE"
  line L0 (75, 57.92) -> (77, 57.92)
  line L1 (77, 57.92) -> (77, 63.92)
  line L2 (77, 63.92) -> (75, 63.92)
  line L3 (75, 63.92) -> (75, 57.92)
ref_plane "工作平面10" through (0, 0, 30) normal (0, 0, 1) x (1, 0, 0) in component "05_CENTERED_FLAT_PSU_CRADLE_OPEN_INTAKE"
sketch "草图10 (6)" plane through (0, 0, 30) normal (0, 0, 1) x (1, 0, 0) in component "05_CENTERED_FLAT_PSU_CRADLE_OPEN_INTAKE"
  line L0 (75, 179.92) -> (77, 179.92)
  line L1 (77, 179.92) -> (77, 185.92)
  line L2 (77, 185.92) -> (75, 185.92)
  line L3 (75, 185.92) -> (75, 179.92)
extrude "PSU chassis edge locating stop (1)" add sketch "草图10 (6)" along normal blind 6 bodies 36 in component "05_CENTERED_FLAT_PSU_CRADLE_OPEN_INTAKE"
ref_plane "工作平面11" through (0, 0, 30) normal (0, 0, 1) x (1, 0, 0) in component "05_CENTERED_FLAT_PSU_CRADLE_OPEN_INTAKE"
sketch "草图11 (2)" plane through (0, 0, 30) normal (0, 0, 1) x (1, 0, 0) in component "05_CENTERED_FLAT_PSU_CRADLE_OPEN_INTAKE"
  line L0 (227.8, 57.92) -> (229.8, 57.92)
  line L1 (229.8, 57.92) -> (229.8, 63.92)
  line L2 (229.8, 63.92) -> (227.8, 63.92)
  line L3 (227.8, 63.92) -> (227.8, 57.92)
extrude "PSU chassis edge locating stop (2)" add sketch "草图11 (2)" along normal blind 6 bodies 36 in component "05_CENTERED_FLAT_PSU_CRADLE_OPEN_INTAKE"
ref_plane "工作平面12" through (0, 0, 30) normal (0, 0, 1) x (1, 0, 0) in component "05_CENTERED_FLAT_PSU_CRADLE_OPEN_INTAKE"
sketch "草图12" plane through (0, 0, 30) normal (0, 0, 1) x (1, 0, 0) in component "05_CENTERED_FLAT_PSU_CRADLE_OPEN_INTAKE"
  line L0 (227.8, 179.92) -> (229.8, 179.92)
  line L1 (229.8, 179.92) -> (229.8, 185.92)
  line L2 (229.8, 185.92) -> (227.8, 185.92)
  line L3 (227.8, 185.92) -> (227.8, 179.92)
extrude "PSU chassis edge locating stop (3)" add sketch "草图12" along normal blind 6 bodies 36 in component "05_CENTERED_FLAT_PSU_CRADLE_OPEN_INTAKE"
ref_plane "工作平面1" through (0, -61.92, 0) normal (0, 1, 0) x (0, 0, 1) in component "06_front_LOW_PSU_RETAINER"
sketch "草图1 (33)" plane through (0, -61.92, 0) normal (0, 1, 0) x (1, 0, 0) in component "06_front_LOW_PSU_RETAINER"
  line L0 (69.4, -30, 123.84) -> (77, -30, 123.84)
  line L1 (77, -30, 123.84) -> (77, -117, 123.84)
  line L2 (77, -117, 123.84) -> (227.8, -117, 123.84)
  line L3 (227.8, -117, 123.84) -> (227.8, -30, 123.84)
  line L4 (227.8, -30, 123.84) -> (235.4, -30, 123.84)
  line L5 (235.4, -30, 123.84) -> (235.4, -125, 123.84)
  line L6 (235.4, -125, 123.84) -> (69.4, -125, 123.84)
  line L7 (69.4, -125, 123.84) -> (69.4, -30, 123.84)
extrude "Low removable PSU retainer" add sketch "草图1 (33)" along normal blind 8 separate body contours L0 L1 L2 L3 L4 L5 L6 L7 in plane through (0, 61.92, 0) normal (0, 1, 0) makes body 37 in component "06_front_LOW_PSU_RETAINER"
ref_plane "工作平面1" through (0, -173.92, 0) normal (0, 1, 0) x (0, 0, 1) in component "06_rear_LOW_PSU_RETAINER"
sketch "草图1 (34)" plane through (0, -173.92, 0) normal (0, 1, 0) x (1, 0, 0) in component "06_rear_LOW_PSU_RETAINER"
  line L0 (69.4, -30, 347.84) -> (77, -30, 347.84)
  line L1 (77, -30, 347.84) -> (77, -117, 347.84)
  line L2 (77, -117, 347.84) -> (227.8, -117, 347.84)
  line L3 (227.8, -117, 347.84) -> (227.8, -30, 347.84)
  line L4 (227.8, -30, 347.84) -> (235.4, -30, 347.84)
  line L5 (235.4, -30, 347.84) -> (235.4, -125, 347.84)
  line L6 (235.4, -125, 347.84) -> (69.4, -125, 347.84)
  line L7 (69.4, -125, 347.84) -> (69.4, -30, 347.84)
extrude "Low removable PSU retainer'" add sketch "草图1 (34)" along normal blind 8 separate body contours L0 L1 L2 L3 L4 L5 L6 L7 in plane through (0, 173.92, 0) normal (0, 1, 0) makes body 38 in component "06_rear_LOW_PSU_RETAINER"
ref_plane "工作平面1" through (0, 0, 30) normal (0, 0, 1) x (1, 0, 0) in component "REF_PSU_FLAT_CENTERED_150x140x86"
sketch "草图1 (35)" plane through (0, 0, 30) normal (0, 0, 1) x (1, 0, 0) in component "REF_PSU_FLAT_CENTERED_150x140x86"
  line L0 (77.4, 51.92) -> (227.4, 51.92)
  line L1 (227.4, 51.92) -> (227.4, 191.92)
  line L2 (227.4, 191.92) -> (77.4, 191.92)
  line L3 (77.4, 191.92) -> (77.4, 51.92)
extrude "Horizontal PSU 150 wide x140 deep x86 high" add sketch "草图1 (35)" along normal blind 86 separate body makes body 39 in component "REF_PSU_FLAT_CENTERED_150x140x86"
ref_plane "工作平面1" through (0, 0, 29.7) normal (0, 0, 1) x (1, 0, 0) in component "REF_PSU_INTAKE_DOWN_MINUS_Z"
sketch "草图1 (36)" plane through (0, 0, 29.7) normal (0, 0, 1) x (1, 0, 0) in component "REF_PSU_INTAKE_DOWN_MINUS_Z"
  circle A0 centre (152.4, 121.92) radius 60
extrude "Downward-facing 120 mm intake marker - approximate" add sketch "草图1 (36)" along normal blind 0.3 separate body makes body 40 in component "REF_PSU_INTAKE_DOWN_MINUS_Z"
ref_plane "工作平面1" through (0, -191.92, 0) normal (0, 1, 0) x (0, 0, 1) in component "REF_PSU_REAR_EXHAUST_PLUS_Y"
sketch "草图1 (37)" plane through (0, -191.92, 0) normal (0, 1, 0) x (1, 0, 0) in component "REF_PSU_REAR_EXHAUST_PLUS_Y"
  line L0 (77.4, -30, 383.84) -> (227.4, -30, 383.84)
  line L1 (227.4, -30, 383.84) -> (227.4, -116, 383.84)
  line L2 (227.4, -116, 383.84) -> (77.4, -116, 383.84)
  line L3 (77.4, -116, 383.84) -> (77.4, -30, 383.84)
extrude "Rear exhaust face direction marker" add sketch "草图1 (37)" along normal blind 0.3 separate body contours L0 L1 L2 L3 in plane through (0, 191.92, 0) normal (0, 1, 0) makes body 41 in component "REF_PSU_REAR_EXHAUST_PLUS_Y"
ref_plane "工作平面13" through (0, 0, 30) normal (0, 0, 1) x (1, 0, 0) in component "05_CENTERED_FLAT_PSU_CRADLE_OPEN_INTAKE"
sketch "草图13" plane through (0, 0, 30) normal (0, 0, 1) x (1, 0, 0) in component "05_CENTERED_FLAT_PSU_CRADLE_OPEN_INTAKE"
  line L0 (75, 74) -> (77, 74)
  line L1 (77, 74) -> (77, 80)
  line L2 (77, 80) -> (75, 80)
  line L3 (75, 80) -> (75, 74)
extrude "PSU chassis edge locating stop" add sketch "草图13" along normal blind 6 bodies 36 in component "05_CENTERED_FLAT_PSU_CRADLE_OPEN_INTAKE"
ref_plane "工作平面14" through (0, 0, 30) normal (0, 0, 1) x (1, 0, 0) in component "05_CENTERED_FLAT_PSU_CRADLE_OPEN_INTAKE"
sketch "草图14" plane through (0, 0, 30) normal (0, 0, 1) x (1, 0, 0) in component "05_CENTERED_FLAT_PSU_CRADLE_OPEN_INTAKE"
  line L0 (75, 164) -> (77, 164)
  line L1 (77, 164) -> (77, 170)
  line L2 (77, 170) -> (75, 170)
  line L3 (75, 170) -> (75, 164)
extrude "PSU chassis edge locating stop (4)" add sketch "草图14" along normal blind 6 bodies 36 in component "05_CENTERED_FLAT_PSU_CRADLE_OPEN_INTAKE"
ref_plane "工作平面15" through (0, 0, 30) normal (0, 0, 1) x (1, 0, 0) in component "05_CENTERED_FLAT_PSU_CRADLE_OPEN_INTAKE"
sketch "草图15" plane through (0, 0, 30) normal (0, 0, 1) x (1, 0, 0) in component "05_CENTERED_FLAT_PSU_CRADLE_OPEN_INTAKE"
  line L0 (227.8, 74) -> (229.8, 74)
  line L1 (229.8, 74) -> (229.8, 80)
  line L2 (229.8, 80) -> (227.8, 80)
  line L3 (227.8, 80) -> (227.8, 74)
extrude "PSU chassis edge locating stop (5)" add sketch "草图15" along normal blind 6 bodies 36 in component "05_CENTERED_FLAT_PSU_CRADLE_OPEN_INTAKE"
ref_plane "工作平面16" through (0, 0, 30) normal (0, 0, 1) x (1, 0, 0) in component "05_CENTERED_FLAT_PSU_CRADLE_OPEN_INTAKE"
sketch "草图16" plane through (0, 0, 30) normal (0, 0, 1) x (1, 0, 0) in component "05_CENTERED_FLAT_PSU_CRADLE_OPEN_INTAKE"
  line L0 (227.8, 164) -> (229.8, 164)
  line L1 (229.8, 164) -> (229.8, 170)
  line L2 (229.8, 170) -> (227.8, 170)
  line L3 (227.8, 170) -> (227.8, 164)
extrude "PSU chassis edge locating stop (6)" add sketch "草图16" along normal blind 6 bodies 36 in component "05_CENTERED_FLAT_PSU_CRADLE_OPEN_INTAKE"
ref_plane "工作平面2" through (0, 0, 29.9) normal (0, 0, 1) x (1, 0, 0) in component "06_front_LOW_PSU_RETAINER"
sketch "草图2 (25)" plane through (0, 0, 29.9) normal (0, 0, 1) x (1, 0, 0) in component "06_front_LOW_PSU_RETAINER"
  line L0 (60, 50) -> (240, 50)
  line L1 (240, 50) -> (240, 190)
  line L2 (240, 190) -> (60, 190)
  line L3 (60, 190) -> (60, 50)
extrude "Clearance above cradle locating stops" cut sketch "草图2 (25)" along normal blind 6.3 bodies 37 in component "06_front_LOW_PSU_RETAINER"
ref_plane "工作平面2" through (0, 0, 29.9) normal (0, 0, 1) x (1, 0, 0) in component "06_rear_LOW_PSU_RETAINER"
sketch "草图2 (26)" plane through (0, 0, 29.9) normal (0, 0, 1) x (1, 0, 0) in component "06_rear_LOW_PSU_RETAINER"
  line L0 (60, 50) -> (240, 50)
  line L1 (240, 50) -> (240, 190)
  line L2 (240, 190) -> (60, 190)
  line L3 (60, 190) -> (60, 50)
extrude "Clearance above cradle locating stops'" cut sketch "草图2 (26)" along normal blind 6.3 bodies 38 in component "06_rear_LOW_PSU_RETAINER"
component "01_PCI_front_INSET_SIDE" placed x (1, 0, 0) y (0, 1, 0) z (0, 0, 1) at (0, 0, 0)
component "01_PCI_rear_INSET_SIDE" placed x (1, 0, 0) y (0, 1, 0) z (0, 0, 1) at (0, 0, 0)
component "01_CPU_front_VERTICAL_SIDE" placed x (1, 0, 0) y (0, 1, 0) z (0, 0, 1) at (0, 0, 0)
component "01_CPU_rear_VERTICAL_SIDE" placed x (1, 0, 0) y (0, 1, 0) z (0, 0, 1) at (0, 0, 0)
component "02_PCI_low_SEAM_PLATE" placed x (1, 0, 0) y (0, 1, 0) z (0, 0, 1) at (0, 0, 0)
component "02_PCI_high_SEAM_PLATE" placed x (1, 0, 0) y (0, 1, 0) z (0, 0, 1) at (0, 0, 0)
component "02_CPU_low_SEAM_PLATE" placed x (1, 0, 0) y (0, 1, 0) z (0, 0, 1) at (0, 0, 0)
component "02_CPU_high_SEAM_PLATE" placed x (1, 0, 0) y (0, 1, 0) z (0, 0, 1) at (0, 0, 0)
component "03_FRONT_MOTHERBOARD_BEAM" placed x (1, 0, 0) y (0, 1, 0) z (0, 0, 1) at (0, 0, 0)
component "03_MID_MOTHERBOARD_BEAM" placed x (1, 0, 0) y (0, 1, 0) z (0, 0, 1) at (0, 0, 0)
component "03_REAR_MOTHERBOARD_BEAM" placed x (1, 0, 0) y (0, 1, 0) z (0, 0, 1) at (0, 0, 0)
component "07_GPU_REAR_TOWER" placed x (1, 0, 0) y (0, 1, 0) z (0, 0, 1) at (0, 0, 0)
component "08_GPU_REAR_SLIDER" placed x (1, 0, 0) y (0, 1, 0) z (0, 0, 1) at (0, 0, 0)
component "09_FRONT_DUAL_FAN_CARRIER" placed x (1, 0, 0) y (0, 1, 0) z (0, 0, 1) at (0, 0, 0)
component "10_GPU_140_FAN_MOUNT" placed x (1, 0, 0) y (0, 1, 0) z (0, 0, 1) at (0, 0, 0)
component "10_CPU_140_FAN_MOUNT" placed x (1, 0, 0) y (0, 1, 0) z (0, 0, 1) at (0, 0, 0)
component "REF_CASE_FAN_GPU_140x140x25" placed x (1, 0, 0) y (0, 1, 0) z (0, 0, 1) at (0, 0, 0)
component "REF_AIRFLOW_GPU_FRONT_TO_REAR" placed x (1, 0, 0) y (0, 1, 0) z (0, 0, 1) at (0, 0, 0)
component "REF_CASE_FAN_CPU_140x140x25" placed x (1, 0, 0) y (0, 1, 0) z (0, 0, 1) at (0, 0, 0)
component "REF_AIRFLOW_CPU_FRONT_TO_REAR" placed x (1, 0, 0) y (0, 1, 0) z (0, 0, 1) at (0, 0, 0)
component "REF_BOARD_304.8x243.84_NUMBERED_HOLES" placed x (1, 0, 0) y (0, 1, 0) z (0, 0, 1) at (0, 0, 0)
component "REF_CPU_RIGHT" placed x (1, 0, 0) y (0, 1, 0) z (0, 0, 1) at (0, 0, 0)
component "REF_MEMORY_RIGHT_FRONT" placed x (1, 0, 0) y (0, 1, 0) z (0, 0, 1) at (0, 0, 0)
component "REF_PRIMARY_PCIE_X126.4_APPROX" placed x (1, 0, 0) y (0, 1, 0) z (0, 0, 1) at (0, 0, 0)
component "REF_SECOND_LONG_PCIE_X60_APPROX" placed x (1, 0, 0) y (0, 1, 0) z (0, 0, 1) at (0, 0, 0)
component "REF_GPU_FANS_TO_MINUS_X" placed x (1, 0, 0) y (0, 1, 0) z (0, 0, 1) at (0, 0, 0)
component "REF_GPU_FAN_MARKERS_MINUS_X" placed x (1, 0, 0) y (0, 1, 0) z (0, 0, 1) at (0, 0, 0)
component "11_LOWER_FRONT_COVER_PCI_HALF" placed x (1, 0, 0) y (0, 1, 0) z (0, 0, 1) at (0, 0, 0)
component "11_LOWER_FRONT_COVER_CPU_HALF" placed x (1, 0, 0) y (0, 1, 0) z (0, 0, 1) at (0, 0, 0)
component "04_front_GROUND_BAR_290mm_FLAT_PSU" placed x (1, 0, 0) y (0, 1, 0) z (0, 0, 1) at (0, 0, 0)
component "04_rear_GROUND_BAR_290mm_FLAT_PSU" placed x (1, 0, 0) y (0, 1, 0) z (0, 0, 1) at (0, 0, 0)
component "05_CENTERED_FLAT_PSU_CRADLE_OPEN_INTAKE" placed x (1, 0, 0) y (0, 1, 0) z (0, 0, 1) at (0, 0, 0)
component "06_front_LOW_PSU_RETAINER" placed x (1, 0, 0) y (0, 1, 0) z (0, 0, 1) at (0, 0, 0)
component "06_rear_LOW_PSU_RETAINER" placed x (1, 0, 0) y (0, 1, 0) z (0, 0, 1) at (0, 0, 0)
component "REF_PSU_FLAT_CENTERED_150x140x86" placed x (1, 0, 0) y (0, 1, 0) z (0, 0, 1) at (0, 0, 0)
component "REF_PSU_INTAKE_DOWN_MINUS_Z" placed x (1, 0, 0) y (0, 1, 0) z (0, 0, 1) at (0, 0, 0)
component "REF_PSU_REAR_EXHAUST_PLUS_Y" placed x (1, 0, 0) y (0, 1, 0) z (0, 0, 1) at (0, 0, 0)
equation "desk_limit = 290 mm" comment "V03 layout review; fixed profiles require regeneration"
equation "footprint_width = 290 mm" comment "V03 layout review; fixed profiles require regeneration"
equation "board_width = 304.8 mm" comment "V03 layout review; fixed profiles require regeneration"
equation "board_depth = 243.84 mm" comment "V03 layout review; fixed profiles require regeneration"
equation "board_bottom_height = 208 mm" comment "V03 layout review; fixed profiles require regeneration"
equation "approx_slot_x = 126.4 mm" comment "V03 layout review; fixed profiles require regeneration"
